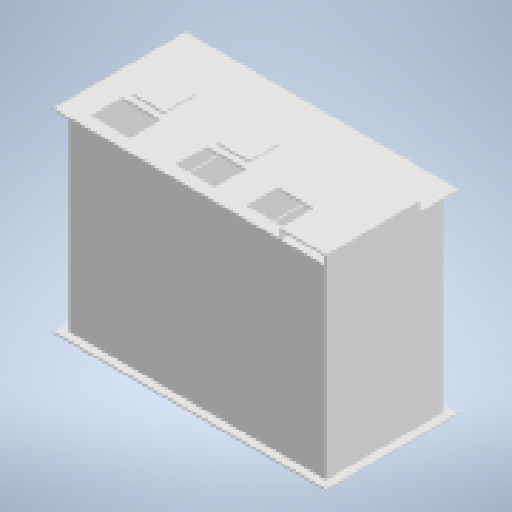
# Autodesk Inventor part: RDS-SPF-3-200-1000 Tank
Saved by Autodesk Inventor 2026 (Build 300175000, 175)
## iProperties
Created: 2026-10-28
Part Number: RDS-SPF-3-200-1000 Tank
Material: Типовые
Document SubType Name: Modeling
Designer: user
Density: 1 g/cm^3
Appearance: По умолчанию
Author: user
Autodesk Inventor part; units mm, degrees
ref_plane "YZ Plane" through (0, 0, 0) normal (1, 0, 0) x (0, 1, 0)
ref_plane "XZ Plane" through (0, 0, 0) normal (0, 1, 0) x (-1, 0, 0)
ref_plane "XY Plane" through (0, 0, 0) normal (0, 0, 1) x (1, 0, 0)
sketch "Эскиз1" plane through (0, 0, 0) normal (0, 1, 0) x (-1, 0, 0)
  line L0 (825, -375) -> (-825, -375)
  line L1 (-825, -375) -> (-825, 375)
  line L2 (-825, 375) -> (825, 375)
  line L3 (825, 375) -> (825, -375)
  line L4 (825, -375) -> (-825, 375) construction
  line L5 (-825, -375) -> (825, 375) construction
  point P0 (0, 0)
  dimension "d0" = 1650
  dimension "d1" = 750
  constraints: 12 end point, 2 midpoint, 2 parallel, 1 horizontal, 1 perpendicular
  measures "d0" distance of L1.end L2.end
  measures "d1" distance of L0.end L1.end
extrude "Выдавливание1" add sketch "Эскиз1" along normal blind 1250
shell "Оболочка1" thickness 10 removed faces 1 at (275, 1250, -125)
sketch "Эскиз2" plane through (0, 0, 0) normal (0, -1, 0) x (1, 0, 0)
  line L0 (-875, -425) -> (875, -425)
  line L1 (875, -425) -> (875, 425)
  line L2 (875, 425) -> (-875, 425)
  line L3 (-875, 425) -> (-875, -425)
  line L4 (-875, -425) -> (875, 425) construction
  line L5 (875, -425) -> (-875, 425) construction
  point P0 (0, 0)
  dimension "d5" = 1750
  dimension "d6" = 850
  constraints: 12 end point, 2 midpoint, 2 parallel, 1 horizontal, 1 perpendicular
  measures "d5" distance of L2.end L1.end
  measures "d6" distance of L1.end L0.end
extrude "Выдавливание2" add sketch "Эскиз2" against normal blind 10
sketch "Эскиз3" plane through (-815, 10, 365) normal (0, 1, 0) x (1, 0, 0)
  line L0 (-10, 740) -> (-10, -10) projected
  line L1 (-10, -10) -> (1640, -10) projected
  line L2 (0, 0) -> (0, 730) projected
  line L3 (1630, 0) -> (0, 0) projected
  line L4 (1640, 740) -> (-10, 740) projected
  line L5 (0, 730) -> (1630, 730) projected
  line L6 (1630, 730) -> (1630, 0) projected
  line L7 (1640, -10) -> (1640, 740) projected
  line L8 (535, 0) -> (545, 0)
  line L9 (545, 0) -> (545, 730)
  line L10 (545, 730) -> (535, 730)
  line L11 (535, 730) -> (535, 0)
  line L12 (1080, 0) -> (1090, 0)
  line L13 (1090, 0) -> (1090, 730)
  line L14 (1090, 730) -> (1080, 730)
  line L15 (1080, 730) -> (1080, 0)
  point P0 (815, 365)
  dimension "d9" = 10
  dimension "d10" = 535
  dimension "d11" = 10
  dimension "d12" = 535
  constraints: 16 end point, 4 parallel, 4 point on line, 2 horizontal, 2 perpendicular
  measures "d9" distance between parallel lines of L9 L11
  measures "d10" distance between parallel lines of L11 L2
  measures "d11" distance between parallel lines of L13 L15
  measures "d12" distance between parallel lines of L15 L9
extrude "Выдавливание3" add sketch "Эскиз3" along normal blind 1050 contours L11 L5 L9 L3 | L15 L5 L13 L3
sketch "Эскиз4" plane through (0, 1250, 0) normal (0, 1, 0) x (1, 0, 0)
  line L0 (-825, 375) -> (-825, -375) projected
  line L1 (-815, -365) -> (-815, 365) projected
  line L2 (825, 375) -> (-825, 375) projected
  line L3 (-815, 365) -> (815, 365) projected
  line L4 (-270, -365) -> (-270, 365) projected
  line L5 (-280, 365) -> (-280, -365) projected
  line L6 (275, -365) -> (275, 365) projected
  line L7 (265, 365) -> (265, -365) projected
  line L8 (815, 365) -> (815, -365) projected
  line L9 (825, -375) -> (825, 375) projected
  line L10 (-825, -375) -> (825, -375) projected
  line L11 (815, -365) -> (-815, -365) projected
  line L12 (-375, -365) -> (-365, -365)
  line L13 (-365, -365) -> (-365, 365)
  line L14 (-365, 365) -> (-375, 365)
  line L15 (-375, 365) -> (-375, -365)
  line L16 (170, 365) -> (180, 365)
  line L17 (180, 365) -> (180, -365)
  line L18 (180, -365) -> (170, -365)
  line L19 (170, -365) -> (170, 365)
  point P0 (0, 0)
  dimension "d15" = 10
  dimension "d16" = 85
  dimension "d17" = 10
  dimension "d18" = 85
  constraints: 16 end point, 4 parallel, 4 point on line, 2 horizontal, 2 perpendicular
  measures "d15" distance between parallel lines of L13 L15
  measures "d16" distance between parallel lines of L5 L13
  measures "d17" distance between parallel lines of L17 L19
  measures "d18" distance between parallel lines of L7 L17
extrude "Выдавливание4" add sketch "Эскиз4" against normal blind 1160 contours L15 L3 L13 L11 | L19 L3 L17 L11
sketch "Эскиз5" plane through (0, 1250, 0) normal (0, 1, 0) x (1, 0, 0)
  line L0 (-875, 425) -> (875, 425)
  line L1 (875, 425) -> (875, -425)
  line L2 (875, -425) -> (-875, -425)
  line L3 (-875, -425) -> (-875, 425)
  line L4 (-875, 425) -> (875, -425) construction
  line L5 (875, 425) -> (-875, -425) construction
  point P0 (0, 0)
  dimension "d21" = 1750
  dimension "d22" = 850
  constraints: 12 end point, 2 midpoint, 2 parallel, 1 horizontal, 1 perpendicular
  measures "d21" distance of L1.end L2.end
  measures "d22" distance of L0.end L1.end
extrude "Выдавливание5" add sketch "Эскиз5" against normal blind 10
sketch "Эскиз6" plane through (0, 1250, 0) normal (0, 1, 0) x (1, 0, 0)
  line L0 (-815, 365) -> (-815, -365) projected
  line L1 (-815, -365) -> (-375, -365) projected
  line L2 (-375, 365) -> (-815, 365) projected
  line L3 (170, 365) -> (-365, 365) projected
  line L4 (-365, -365) -> (170, -365) projected
  line L5 (180, -365) -> (815, -365) projected
  line L6 (180, 365) -> (180, -365) projected
  line L7 (815, 365) -> (180, 365) projected
  line L8 (815, -365) -> (815, 365) projected
  line L9 (180, -365) -> (815, -365) projected
  line L10 (815, 365) -> (180, 365) projected
  line L11 (815, -365) -> (815, 365) projected
  line L12 (825, 375) -> (825, -375) projected
  line L13 (275, -365) -> (265, -365) projected
  line L14 (265, 365) -> (265, -365) projected
  line L15 (275, -365) -> (275, 365) projected
  line L16 (275, -365) -> (265, -365) projected
  line L17 (275, -365) -> (275, 365) projected
  line L18 (265, 365) -> (275, 365) projected
  line L19 (265, 365) -> (265, -365) projected
  line L20 (-365, 365) -> (-365, -365) projected
  line L21 (-375, -365) -> (-365, -365) projected
  line L22 (-815, -365) -> (-280, -365) projected
  line L23 (-270, -365) -> (-280, -365) projected
  line L24 (-375, -365) -> (-375, 365) projected
  line L25 (-815, 365) -> (-815, -365) projected
  line L26 (-815, 365) -> (-815, -365) projected
  line L27 (-815, 365) -> (-815, -365) projected
  line L28 (-825, -375) -> (-825, 375) projected
  line L29 (-825, 375) -> (-825, -375) projected
  line L30 (-280, 365) -> (-815, 365) projected
  line L31 (815, 365) -> (275, 365) projected
  line L32 (170, -365) -> (170, 365) projected
  line L33 (-280, 365) -> (-270, 365) projected
  line L34 (-365, 365) -> (-365, -365) projected
  line L35 (-365, 365) -> (-365, -365) projected
  line L36 (170, 365) -> (-365, 365) projected
  line L37 (170, -365) -> (170, 365) projected
  line L38 (-365, -365) -> (170, -365) projected
  line L39 (180, 365) -> (180, -365) projected
  line L40 (180, 365) -> (180, -365) projected
  line L41 (180, 365) -> (180, -365) projected
  line L42 (180, 365) -> (180, -365) projected
  line L43 (815, -365) -> (815, 365) projected
  line L44 (815, -365) -> (815, 365) projected
  line L45 (815, -365) -> (815, 365) projected
  line L46 (170, -365) -> (180, -365) projected
  line L47 (170, -365) -> (170, 365) projected
  line L48 (170, -365) -> (180, -365) projected
  line L49 (170, -365) -> (170, 365) projected
  line L50 (180, 365) -> (170, 365) projected
  line L51 (180, 365) -> (180, -365) projected
  line L52 (265, -365) -> (265, 365) projected
  line L53 (265, 365) -> (265, -365) projected
  line L54 (275, 365) -> (275, -365) projected
  line L55 (275, -365) -> (275, 365) projected
  line L56 (-825, 375) -> (825, 375) projected
  line L57 (-270, -365) -> (265, -365) projected
  line L58 (275, -365) -> (815, -365) projected
  line L59 (170, -365) -> (170, 365) projected
  line L60 (170, -365) -> (170, 365) projected
  line L61 (180, 365) -> (170, 365) projected
  line L62 (265, 365) -> (-270, 365) projected
  line L63 (265, 365) -> (275, 365) projected
  line L64 (815, 365) -> (180, 365) projected
  line L65 (180, 365) -> (170, 365) projected
  line L66 (170, 365) -> (-365, 365) projected
  line L67 (-365, 365) -> (-375, 365) projected
  line L68 (-375, 365) -> (-815, 365) projected
  line L69 (-280, 365) -> (-815, 365) projected
  line L70 (-280, 365) -> (-270, 365) projected
  line L71 (265, 365) -> (-270, 365) projected
  line L72 (265, 365) -> (275, 365) projected
  line L73 (815, 365) -> (275, 365) projected
  line L74 (180, -365) -> (815, -365) projected
  line L75 (275, -365) -> (815, -365) projected
  line L76 (275, -365) -> (265, -365) projected
  line L77 (-270, -365) -> (265, -365) projected
  line L78 (-270, -365) -> (-280, -365) projected
  line L79 (-815, -365) -> (-280, -365) projected
  line L80 (-815, -365) -> (-375, -365) projected
  line L81 (-375, -365) -> (-365, -365) projected
  line L82 (-365, -365) -> (170, -365) projected
  line L83 (170, -365) -> (180, -365) projected
  line L84 (-825, -375) -> (825, -375) projected
  line L85 (825, 375) -> (-825, 375) projected
  line L86 (825, -375) -> (825, 375) projected
  line L87 (-825, 375) -> (825, 375) projected
  line L88 (825, 375) -> (-825, 375) projected
  line L89 (825, 375) -> (825, -375) projected
  line L90 (825, -375) -> (825, 375) projected
  line L91 (825, -375) -> (-825, -375) projected
  line L92 (-825, -375) -> (825, -375) projected
  line L93 (825, -375) -> (-825, -375) projected
  line L94 (-280, -365) -> (-280, 365) projected
  line L95 (265, -365) -> (265, 365) projected
  line L96 (265, -365) -> (265, 365) projected
  line L97 (265, 365) -> (-270, 365) projected
  line L98 (-270, 365) -> (-270, -365) projected
  line L99 (-270, -365) -> (265, -365) projected
  line L100 (275, 365) -> (275, -365) projected
  line L101 (-280, -365) -> (-280, 365) projected
  line L102 (-280, 365) -> (-815, 365) projected
  line L103 (-815, 365) -> (-815, -365) projected
  line L104 (-815, -365) -> (-280, -365) projected
  line L105 (275, 365) -> (275, -365) projected
  line L106 (275, -365) -> (815, -365) projected
  line L107 (815, -365) -> (815, 365) projected
  line L108 (815, 365) -> (275, 365) projected
  line L109 (-270, 365) -> (-270, -365) projected
  line L110 (-825, -375) -> (-825, 375) projected
  line L111 (-375, -365) -> (-375, 365) projected
  line L112 (-375, -365) -> (-375, 365) projected
  line L113 (-815, -365) -> (-375, -365) projected
  line L114 (-815, 365) -> (-815, -365) projected
  line L115 (-375, 365) -> (-815, 365) projected
  line L116 (-365, 365) -> (-375, 365) projected
  line L117 (-375, -365) -> (-375, 365) projected
  line L118 (-375, -365) -> (-375, 365) projected
  line L119 (-375, -365) -> (-365, -365) projected
  line L120 (-375, -365) -> (-375, 365) projected
  line L121 (-365, 365) -> (-375, 365) projected
  line L122 (-365, 365) -> (-365, -365) projected
  line L123 (-270, -365) -> (-270, 365) projected
  line L124 (-270, 365) -> (-270, -365) projected
  line L125 (-270, -365) -> (-270, 365) projected
  line L126 (-270, -365) -> (-280, -365) projected
  line L127 (-270, -365) -> (-270, 365) projected
  line L128 (-280, 365) -> (-270, 365) projected
  line L129 (-280, 365) -> (-280, -365) projected
  line L130 (-280, 365) -> (-280, -365) projected
  line L131 (-280, -365) -> (-280, 365) projected
  line L132 (-280, 365) -> (-280, -365) projected
  line L133 (-825, 375) -> (-825, -375) projected
  line L134 (-365, 365) -> (-365, -365) projected
  line L135 (-365, 365) -> (-365, -365) projected
  line L136 (-715, -145) -> (-465, -145)
  line L137 (-465, -145) -> (-465, -345)
  line L138 (-465, -345) -> (-715, -345)
  line L139 (-715, -345) -> (-715, -145)
  line L140 (-170, -145) -> (80, -145)
  line L141 (80, -145) -> (80, -345)
  line L142 (80, -345) -> (-170, -345)
  line L143 (-170, -345) -> (-170, -145)
  line L144 (285, -145) -> (535, -145)
  line L145 (535, -145) -> (535, -345)
  line L146 (535, -345) -> (285, -345)
  line L147 (285, -345) -> (285, -145)
  point P0 (0, 0)
  dimension "d25" = 250
  dimension "d26" = 200
  dimension "d27" = 250
  dimension "d28" = 200
  dimension "d29" = 250
  dimension "d30" = 200
  dimension "d31" = 20
  dimension "d32" = 100
  dimension "d33" = 20
  dimension "d34" = 100
  dimension "d35" = 20
  dimension "d36" = 280
  constraints: 24 end point, 6 parallel, 3 horizontal, 3 perpendicular, 9 other
  measures "d25" distance of L137.end L138.end
  measures "d26" distance of L136.end L137.end
  measures "d27" distance of L141.end L142.end
  measures "d28" distance of L140.end L141.end
  measures "d29" distance of L145.end L146.end
  measures "d30" distance of L144.end L145.end
  measures "d31" distance from line of L138 L0.end
  measures "d32" horizontal distance of L138.end L0.end
  measures "d33" distance between parallel lines of L4 L142
  measures "d34" distance between parallel lines of L143 L98
  measures "d35" distance from line of L5 L145.end
  measures "d36" distance between parallel lines of L8 L145
extrude "Выдавливание6" cut sketch "Эскиз6" against normal blind 10 contours L136 L137 L138 L139 | L140 L141 L142 L143 | L144 L145 L146 L147
sketch "Эскиз7" plane through (0, 1250, 0) normal (0, 1, 0) x (1, 0, 0)
  line L0 (815, 365) -> (180, 365) projected
  line L1 (170, -365) -> (180, -365) projected
  line L2 (170, -365) -> (170, 365) projected
  line L3 (170, -365) -> (180, -365) projected
  line L4 (170, -365) -> (170, 365) projected
  line L5 (180, 365) -> (170, 365) projected
  line L6 (180, 365) -> (180, -365) projected
  line L7 (265, -365) -> (265, 365) projected
  line L8 (265, 365) -> (265, -365) projected
  line L9 (275, 365) -> (275, -365) projected
  line L10 (275, -365) -> (275, 365) projected
  line L11 (265, 365) -> (275, 365) projected
  line L12 (815, 365) -> (275, 365) projected
  line L13 (180, -365) -> (815, -365) projected
  line L14 (815, -365) -> (815, 365) projected
  line L15 (815, -365) -> (815, 365) projected
  line L16 (815, -365) -> (815, 365) projected
  line L17 (815, -365) -> (815, 365) projected
  line L18 (170, -365) -> (170, 365) projected
  line L19 (180, 365) -> (180, -365) projected
  line L20 (180, 365) -> (180, -365) projected
  line L21 (180, 365) -> (180, -365) projected
  line L22 (180, 365) -> (180, -365) projected
  line L23 (-825, 375) -> (-825, -375) projected
  line L24 (-280, 365) -> (-815, 365) projected
  line L25 (-365, 365) -> (-365, -365) projected
  line L26 (-170, -345) -> (-170, -145) projected
  line L27 (-170, -145) -> (-170, -345) projected
  line L28 (-465, -345) -> (-715, -345) projected
  line L29 (-715, -145) -> (-465, -145) projected
  line L30 (-465, -145) -> (-715, -145) projected
  line L31 (-375, 365) -> (-815, 365) projected
  line L32 (-815, 365) -> (-815, -365) projected
  line L33 (-815, -365) -> (-375, -365) projected
  line L34 (-365, -365) -> (170, -365) projected
  line L35 (170, 365) -> (-365, 365) projected
  line L36 (535, -345) -> (535, -145) projected
  line L37 (535, -145) -> (285, -145) projected
  line L38 (285, -145) -> (285, -345) projected
  line L39 (285, -345) -> (535, -345) projected
  line L40 (180, 365) -> (180, -365) projected
  line L41 (815, 365) -> (180, 365) projected
  line L42 (815, -365) -> (815, 365) projected
  line L43 (180, -365) -> (815, -365) projected
  line L44 (170, -365) -> (170, 365) projected
  line L45 (170, -365) -> (170, 365) projected
  line L46 (180, 365) -> (170, 365) projected
  line L47 (265, 365) -> (-270, 365) projected
  line L48 (275, -365) -> (815, -365) projected
  line L49 (825, 375) -> (825, -375) projected
  line L50 (825, -375) -> (825, 375) projected
  line L51 (815, 365) -> (180, 365) projected
  line L52 (180, 365) -> (170, 365) projected
  line L53 (170, 365) -> (-365, 365) projected
  line L54 (-365, 365) -> (-375, 365) projected
  line L55 (-375, 365) -> (-815, 365) projected
  line L56 (-280, 365) -> (-815, 365) projected
  line L57 (-280, 365) -> (-270, 365) projected
  line L58 (265, 365) -> (-270, 365) projected
  line L59 (265, 365) -> (275, 365) projected
  line L60 (815, 365) -> (275, 365) projected
  line L61 (825, 375) -> (-825, 375) projected
  line L62 (-825, 375) -> (825, 375) projected
  line L63 (825, 375) -> (-825, 375) projected
  line L64 (180, -365) -> (815, -365) projected
  line L65 (275, -365) -> (815, -365) projected
  line L66 (275, -365) -> (265, -365) projected
  line L67 (-270, -365) -> (265, -365) projected
  line L68 (-270, -365) -> (-280, -365) projected
  line L69 (-815, -365) -> (-280, -365) projected
  line L70 (-815, -365) -> (-375, -365) projected
  line L71 (-375, -365) -> (-365, -365) projected
  line L72 (-365, -365) -> (170, -365) projected
  line L73 (170, -365) -> (180, -365) projected
  line L74 (-825, -375) -> (825, -375) projected
  line L75 (825, -375) -> (-825, -375) projected
  line L76 (-825, -375) -> (825, -375) projected
  line L77 (825, -375) -> (-825, -375) projected
  line L78 (-375, -365) -> (-375, 365) projected
  line L79 (825, -375) -> (825, 375) projected
  line L80 (535, -345) -> (285, -345) projected
  line L81 (-270, -365) -> (265, -365) projected
  line L82 (-715, -345) -> (-465, -345) projected
  line L83 (285, -345) -> (535, -345) projected
  line L84 (80, -345) -> (-170, -345) projected
  line L85 (-170, -345) -> (80, -345) projected
  line L86 (80, -345) -> (-170, -345) projected
  line L87 (-170, -345) -> (80, -345) projected
  line L88 (80, -345) -> (80, -145) projected
  line L89 (80, -145) -> (80, -345) projected
  line L90 (80, -145) -> (80, -345) projected
  line L91 (80, -345) -> (80, -145) projected
  line L92 (-170, -145) -> (80, -145) projected
  line L93 (-170, -145) -> (80, -145) projected
  line L94 (80, -145) -> (-170, -145) projected
  line L95 (-280, -365) -> (-280, 365) projected
  line L96 (265, -365) -> (265, 365) projected
  line L97 (265, -365) -> (265, 365) projected
  line L98 (265, 365) -> (-270, 365) projected
  line L99 (-270, 365) -> (-270, -365) projected
  line L100 (-270, -365) -> (265, -365) projected
  line L101 (275, 365) -> (275, -365) projected
  line L102 (-280, -365) -> (-280, 365) projected
  line L103 (-280, 365) -> (-815, 365) projected
  line L104 (-815, 365) -> (-815, -365) projected
  line L105 (-815, -365) -> (-280, -365) projected
  line L106 (275, 365) -> (275, -365) projected
  line L107 (275, -365) -> (815, -365) projected
  line L108 (815, -365) -> (815, 365) projected
  line L109 (815, 365) -> (275, 365) projected
  line L110 (-715, -145) -> (-465, -145) projected
  line L111 (-825, 375) -> (825, 375) projected
  line L112 (-170, -145) -> (-170, -345) projected
  line L113 (80, -145) -> (-170, -145) projected
  line L114 (80, -345) -> (80, -145) projected
  line L115 (80, -145) -> (-170, -145) projected
  line L116 (-170, -145) -> (-170, -345) projected
  line L117 (-170, -345) -> (80, -345) projected
  line L118 (-365, 365) -> (-365, -365) projected
  line L119 (170, 365) -> (-365, 365) projected
  line L120 (170, -365) -> (170, 365) projected
  line L121 (-365, -365) -> (170, -365) projected
  line L122 (-170, -345) -> (-170, -145) projected
  line L123 (-270, 365) -> (-270, -365) projected
  line L124 (-280, 365) -> (-270, 365) projected
  line L125 (-365, 365) -> (-365, -365) projected
  line L126 (-365, 365) -> (-365, -365) projected
  line L127 (-365, 365) -> (-375, 365) projected
  line L128 (-375, -365) -> (-365, -365) projected
  line L129 (-375, -365) -> (-375, 365) projected
  line L130 (-365, 365) -> (-375, 365) projected
  line L131 (-365, 365) -> (-365, -365) projected
  line L132 (-270, -365) -> (-270, 365) projected
  line L133 (-270, 365) -> (-270, -365) projected
  line L134 (-270, -365) -> (-270, 365) projected
  line L135 (-270, -365) -> (-280, -365) projected
  line L136 (-270, -365) -> (-270, 365) projected
  line L137 (-280, 365) -> (-270, 365) projected
  line L138 (-280, 365) -> (-280, -365) projected
  line L139 (-280, 365) -> (-280, -365) projected
  line L140 (-280, -365) -> (-280, 365) projected
  line L141 (-280, 365) -> (-280, -365) projected
  line L142 (-465, -345) -> (-715, -345) projected
  line L143 (-715, -345) -> (-465, -345) projected
  line L144 (-715, -345) -> (-715, -145) projected
  line L145 (-715, -345) -> (-715, -145) projected
  line L146 (-715, -145) -> (-715, -345) projected
  line L147 (-715, -145) -> (-715, -345) projected
  line L148 (-465, -145) -> (-715, -145) projected
  line L149 (-465, -345) -> (-465, -145) projected
  line L150 (-465, -145) -> (-715, -145) projected
  line L151 (-715, -145) -> (-715, -345) projected
  line L152 (-715, -345) -> (-465, -345) projected
  line L153 (-375, -365) -> (-375, 365) projected
  line L154 (-815, -365) -> (-375, -365) projected
  line L155 (-815, 365) -> (-815, -365) projected
  line L156 (-375, 365) -> (-815, 365) projected
  line L157 (-365, 365) -> (-365, -365) projected
  line L158 (-375, -365) -> (-365, -365) projected
  line L159 (-815, -365) -> (-280, -365) projected
  line L160 (-270, -365) -> (-280, -365) projected
  line L161 (-375, -365) -> (-375, 365) projected
  line L162 (-815, 365) -> (-815, -365) projected
  line L163 (-815, 365) -> (-815, -365) projected
  line L164 (-815, 365) -> (-815, -365) projected
  line L165 (-825, -375) -> (-825, 375) projected
  line L166 (-825, 375) -> (-825, -375) projected
  line L167 (-825, -375) -> (-825, 375) projected
  line L168 (-375, -365) -> (-375, 365) projected
  line L169 (-375, -365) -> (-375, 365) projected
  line L170 (-465, -345) -> (-465, -145) projected
  line L171 (-465, -145) -> (-465, -345) projected
  line L172 (-465, -145) -> (-465, -345) projected
  line L173 (-465, -345) -> (-465, -145) projected
  line L174 (825, 375) -> (825, -375) projected
  line L175 (285, -145) -> (285, -345) projected
  line L176 (285, -345) -> (285, -145) projected
  line L177 (535, -145) -> (285, -145) projected
  line L178 (285, -145) -> (535, -145) projected
  line L179 (535, -345) -> (535, -145) projected
  line L180 (535, -145) -> (535, -345) projected
  line L181 (535, -345) -> (285, -345) projected
  line L182 (285, -345) -> (535, -345) projected
  line L183 (285, -345) -> (285, -145) projected
  line L184 (285, -145) -> (285, -345) projected
  line L185 (285, -145) -> (535, -145) projected
  line L186 (535, -145) -> (285, -145) projected
  line L187 (535, -145) -> (535, -345) projected
  line L188 (535, -345) -> (535, -145) projected
  line L189 (275, -365) -> (265, -365) projected
  line L190 (265, 365) -> (265, -365) projected
  line L191 (275, -365) -> (275, 365) projected
  line L192 (275, -365) -> (265, -365) projected
  line L193 (275, -365) -> (275, 365) projected
  line L194 (265, 365) -> (275, 365) projected
  line L195 (265, 365) -> (265, -365) projected
  line L196 (-690, 100) -> (-490, 100)
  line L197 (-490, 100) -> (-490, -100)
  line L198 (-490, -100) -> (-690, -100)
  line L199 (-690, -100) -> (-690, 100)
  line L200 (-145, 100) -> (55, 100)
  line L201 (55, 100) -> (55, -100)
  line L202 (55, -100) -> (-145, -100)
  line L203 (-145, -100) -> (-145, 100)
  point P0 (0, 0)
  dimension "d39" = 200
  dimension "d40" = 200
  dimension "d41" = 200
  dimension "d42" = 200
  dimension "d43" = 100
  dimension "d44" = 125
  dimension "d45" = 125
  dimension "d46" = 100
  constraints: 16 end point, 4 parallel, 2 horizontal, 2 perpendicular, 23 other
  measures "d39" distance of L197.end L198.end
  measures "d40" distance of L196.end L197.end
  measures "d41" distance of L201.end L202.end
  measures "d42" distance of L200.end L201.end
  measures "d43" distance from line of L196 point (0, 0)
  measures "d44" distance between parallel lines of L199 L32
  measures "d45" distance between parallel lines of L203 L99
  measures "d46" distance from line of point (0, 0) L200
extrude "Выдавливание7" add sketch "Эскиз7" along normal blind 10 contours L196 L197 L198 L199 | L200 L201 L202 L203
sketch "Эскиз8" plane through (-875, 1250, 425) normal (0, 0, 1) x (1, 0, 0)
  line L0 (0, 0) -> (1750, 0) projected
  line L1 (1750, 0) -> (1750, -10) projected
  line L2 (1410, 0) -> (1410, -10)
  line L3 (1410, 0) -> (1410, -10) projected
  line L4 (1750, 0) -> (1750, 60)
  line L5 (1750, 60) -> (1450, 60)
  line L6 (1450, 60) -> (1450, 0)
  line L7 (1450, 0) -> (1460, 0)
  line L8 (1460, 0) -> (1460, 50)
  line L9 (1460, 50) -> (1740, 50)
  line L10 (1740, 50) -> (1740, 0)
  line L11 (1740, 0) -> (1750, 0)
  point P0 (875, -1250)
  point P1 (1690, -10)
  point P2 (1700, -10)
  dimension "d49" = 60
  dimension "d50" = 300
  dimension "d51" = 60
  dimension "d52" = 10
  dimension "d53" = 50
  dimension "d54" = 280
  dimension "d55" = 50
  constraints: 18 end point, 4 perpendicular, 3 point on line, 1 vertical
  measures "d49" distance of L0.end L4.end
  measures "d50" distance of L4.end L5.end
  measures "d51" distance of L5.end L6.end
  measures "d52" distance of L6.end L7.end
  measures "d53" distance of L7.end L8.end
  measures "d54" distance of L8.end L9.end
  measures "d55" distance of L9.end L10.end
extrude "Выдавливание8" add sketch "Эскиз8" against normal blind 600 contours L6 L5 L4 L0 L10 L9 L8
